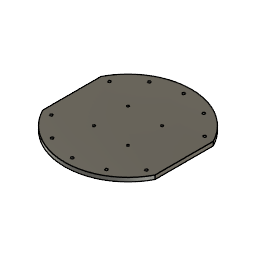
Assembly (Autodesk Fusion 360 archive; units mm, degrees)
design "Upper Chasis"
part number: 2026-04-02-12-40-59-312
Autodesk Fusion 360 part; units mm, degrees
sketch "Sketch1" plane through (0, 0, 0) normal (0, 0, 1) x (-1, 0, 0)
  line L0 (-80, 0) -> (80, 0) construction
  line L1 (-71, -12.5) -> (-10, -12.5)
  line L2 (-10, -12.5) -> (-10, 12.5)
  line L3 (-10, 12.5) -> (-71, 12.5)
  line L4 (-71, 12.5) -> (-71, -12.5)
  line L5 (-71, -36.8646) -> (-71, 36.8646)
  line L6 (0, -80) -> (0, 80) construction
  line L7 (10, -12.5) -> (10, 12.5)
  line L8 (10, 12.5) -> (71, 12.5)
  line L9 (71, -12.5) -> (10, -12.5)
  line L10 (71, 12.5) -> (71, -12.5)
  line L11 (71, -36.8646) -> (71, 36.8646)
  arc A0 (71, 36.8646) -> (-71, 36.8646) centre (0, 0) ccw
  arc A1 (-71, -36.8646) -> (71, -36.8646) centre (0, 0) ccw
  dimension "d6" = 160
  dimension "d7" = 61
  dimension "d8" = 25
  dimension "d9" = 10
  dimension "d10" = 71
  constraint coincident A0.centre A1.centre
  constraint horizontal L0
  constraint horizontal L1
  constraint vertical L2
  constraint horizontal L3
  constraint vertical L4
  constraint symmetric L0 L1 L3
  constraint perpendicular L3 L5
  constraint coincident L6.start A1
  constraint coincident L6.end A0
  constraint vertical L6
  constraint symmetric L1.start L6 L9.start
  constraint symmetric L1.end L6 L7.start
  constraint symmetric L2.end L6 L7.end
  constraint symmetric L3.end L6 L8.end
  constraint symmetric L5.start L6 L11.start
  constraint symmetric L5.end L6 L11.end
  constraint concentric A0 A1
  measures "d6" diameter of A0
  measures "d7" distance of L1.start L1.end
  measures "d8" distance of L1.start L3.end
  measures "d9" distance of A0.centre L2
  measures "d10" distance of A0.centre L5
extrude "Extrude3" add sketch "Sketch1" along normal blind 5
sketch "Sketch3" plane through (0, 0, 5) normal (0, 0, 1) x (-1, 0, 0)
  line L0 (-71, 36.8646) -> (-71, 12.5)
  line L1 (-71, 12.5) -> (-10, 12.5)
  line L2 (-10, 12.5) -> (-10, -12.5)
  line L3 (-10, -12.5) -> (-71, -12.5)
  line L4 (-71, -12.5) -> (-71, -36.8646)
  arc A0 (-71, -36.8646) -> (71, -36.8646) centre (0, 0) ccw
  line L5 (71, -36.8646) -> (71, -12.5)
  line L6 (71, -12.5) -> (10, -12.5)
  line L7 (10, -12.5) -> (10, 12.5)
  line L8 (10, 12.5) -> (71, 12.5)
  line L9 (71, 12.5) -> (71, 36.8646)
  arc A1 (71, 36.8646) -> (-71, 36.8646) centre (0, 0) ccw
  line L10 (-70, 0) -> (70, 0) construction
  line L11 (0, 80) -> (0, -80) construction
  line L12 (21.5, -21.5) -> (-21.5, -21.5)
  line L13 (-21.5, -21.5) -> (-21.5, 21.5)
  line L14 (-21.5, 21.5) -> (21.5, 21.5)
  line L15 (21.5, 21.5) -> (21.5, -21.5)
  point P0 (-60.0095, 36.8646)
  point P1 (-34.3452, 61.4862)
  point P2 (0.0774, 70.4282)
  point P3 (34.4802, 61.4105)
  point P4 (60.0904, 36.7327)
  point P5 (-60.0095, -36.8646)
  point P6 (-34.3452, -61.4862)
  point P7 (0.0774, -70.4282)
  point P8 (34.4802, -61.4105)
  point P9 (60.0904, -36.7327)
  point P10 (21.5, -21.5)
  point P11 (-21.5, -21.5)
  point P12 (21.5, 21.5)
  point P13 (-21.5, 21.5)
  dimension "d20" = -117
  dimension "d25" = 43
  dimension "d26" = 43
  constraint perpendicular L7 L10
  constraint symmetric P0 L10 P5
  constraint symmetric P1 L10 P6
  constraint symmetric P2 L10 P7
  constraint symmetric P3 L10 P8
  constraint symmetric P4 L10 P9
  constraint midpoint A1 L11.start
  constraint midpoint A0 L11.end
  constraint horizontal L12
  constraint vertical L13
  constraint horizontal L14
  constraint vertical L15
  constraint symmetric L11 L13 L15
  constraint symmetric L10 L12 L14
  constraint coincident P10 L12.start
  constraint coincident P11 L12.end
  constraint coincident P12 L14.end
  constraint coincident P13 L13.end
  measures "d25" distance of P10 P11
  measures "d26" distance of P10 P12
hole "Hole2" at (-60.0904, 36.7327, 5) at (-34.4802, 61.4105, 5) at (-0.0774, 70.4282, 5) at (34.3452, 61.4862, 5) at (60.0095, 36.8646, 5) at (-60.0904, -36.7327, 5) at (-34.4802, -61.4105, 5) at (-0.0774, -70.4282, 5) at (34.3452, -61.4862, 5) at (60.0095, -36.8646, 5) direction (0, 0, -1) diameter 3.2 end through all
hole "Hole3" at (-21.5, 21.5, 5) at (21.5, 21.5, 5) at (-21.5, -21.5, 5) at (21.5, -21.5, 5) direction (0, 0, -1) diameter 2.7 end through all
equation "chasis_diameter = 160 mm"
equation "main_layer_thickness = 30 mm"
equation "motor_L = 21 mm"
equation "total_motor_body_length = 61 mm"
equation "standoff_height = 50 mm"
equation "d6 = chasis_diameter"

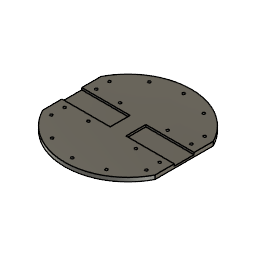
design "Chasis"
part number: 2026-04-02-12-40-59-312
Autodesk Fusion 360 part; units mm, degrees
sketch "Sketch1" plane through (0, 0, 0) normal (0, 0, 1) x (-1, 0, 0)
  line L0 (-80, 0) -> (80, 0) construction
  line L1 (-71, -12.5) -> (-10, -12.5)
  line L2 (-10, -12.5) -> (-10, 12.5)
  line L3 (-10, 12.5) -> (-71, 12.5)
  line L4 (-71, 12.5) -> (-71, -12.5)
  line L5 (-71, -36.8646) -> (-71, 36.8646)
  line L6 (0, -80) -> (0, 80) construction
  line L7 (10, -12.5) -> (10, 12.5)
  line L8 (10, 12.5) -> (71, 12.5)
  line L9 (71, -12.5) -> (10, -12.5)
  line L10 (71, 12.5) -> (71, -12.5)
  line L11 (71, -36.8646) -> (71, 36.8646)
  arc A0 (71, 36.8646) -> (-71, 36.8646) centre (0, 0) ccw
  arc A1 (-71, -36.8646) -> (71, -36.8646) centre (0, 0) ccw
  dimension "d6" = 160
  dimension "d7" = 61
  dimension "d8" = 25
  dimension "d9" = 10
  dimension "d10" = 71
  constraint coincident A0.centre A1.centre
  constraint horizontal L0
  constraint horizontal L1
  constraint vertical L2
  constraint horizontal L3
  constraint vertical L4
  constraint symmetric L0 L1 L3
  constraint perpendicular L3 L5
  constraint coincident L6.start A1
  constraint coincident L6.end A0
  constraint vertical L6
  constraint symmetric L1.start L6 L9.start
  constraint symmetric L1.end L6 L7.start
  constraint symmetric L2.end L6 L7.end
  constraint symmetric L3.end L6 L8.end
  constraint symmetric L5.start L6 L11.start
  constraint symmetric L5.end L6 L11.end
  constraint concentric A0 A1
  measures "d6" diameter of A0
  measures "d7" distance of L1.start L1.end
  measures "d8" distance of L1.start L3.end
  measures "d9" distance of A0.centre L2
  measures "d10" distance of A0.centre L5
extrude "Extrude1" add sketch "Sketch1" along normal blind 5 contours L1 L2 L3 L5 L7 L8 L9 L11 A0 A1
sketch "Sketch2" plane through (0, 0, 5) normal (0, 0, 1) x (-1, 0, 0)
  line L0 (-71, -12.5) -> (-71, -36.8646)
  arc A0 (-71, -36.8646) -> (71, -36.8646) centre (0, 0) ccw
  line L1 (71, -36.8646) -> (71, -12.5)
  line L2 (71, -12.5) -> (10, -12.5)
  line L3 (10, -12.5) -> (10, 12.5)
  line L4 (10, 12.5) -> (71, 12.5)
  line L5 (71, 12.5) -> (71, 36.8646)
  arc A1 (71, 36.8646) -> (-71, 36.8646) centre (0, 0) ccw
  line L6 (-71, 36.8646) -> (-71, 12.5)
  line L7 (-71, 12.5) -> (-10, 12.5)
  line L8 (-10, 12.5) -> (-10, -12.5)
  line L9 (-10, -12.5) -> (-71, -12.5)
  line L10 (-71, 12.5) -> (-10, 12.5)
  line L11 (-10, 12.5) -> (-10, -12.5)
  line L12 (-10, -12.5) -> (-71, -12.5)
  line L13 (10, 12.5) -> (71, 12.5)
  line L14 (10, -12.5) -> (10, 12.5)
  line L15 (71, -12.5) -> (10, -12.5)
  line L16 (-71, -12.5) -> (-71, 12.5)
  line L17 (71, -12.5) -> (71, 12.5)
  constraint coincident L0.start L9.end
  constraint coincident L6.end L7.start
  constraint coincident L1.end L2.start
  constraint coincident L4.end L5.start
extrude "Extrude2" add sketch "Sketch2" against normal blind 2.5 contours L7 L8 L9 L10 L11 L12 L16 | L2 L3 L4 L13 L14 L15 L17
move_body "Move1" bodies 1 to x (1, 0, 0) y (0, -1, 0) z (0, 0, -1) at (0, 0, 0)
move_body "Move2" bodies 1 to x (1, 0, 0) y (0, 1, 0) z (0, 0, 1) at (0, 0, 5)
sketch "Sketch3" plane through (0, 0, 5) normal (0, 0, 1) x (-1, 0, 0)
  line L0 (-71, 36.8646) -> (-71, 12.5)
  line L1 (-71, 12.5) -> (-10, 12.5)
  line L2 (-10, 12.5) -> (-10, -12.5)
  line L3 (-10, -12.5) -> (-71, -12.5)
  line L4 (-71, -12.5) -> (-71, -36.8646)
  arc A0 (-71, -36.8646) -> (71, -36.8646) centre (0, 0) ccw
  line L5 (71, -36.8646) -> (71, -12.5)
  line L6 (71, -12.5) -> (10, -12.5)
  line L7 (10, -12.5) -> (10, 12.5)
  line L8 (10, 12.5) -> (71, 12.5)
  line L9 (71, 12.5) -> (71, 36.8646)
  arc A1 (71, 36.8646) -> (-71, 36.8646) centre (0, 0) ccw
  line L10 (-70, 0) -> (70, 0) construction
  line L11 (0, 80) -> (0, -80) construction
  point P0 (-60.0095, 36.8646)
  point P1 (-34.3452, 61.4862)
  point P2 (0.0774, 70.4282)
  point P3 (34.4802, 61.4105)
  point P4 (60.0904, 36.7327)
  point P5 (-60.0095, -36.8646)
  point P6 (-34.3452, -61.4862)
  point P7 (0.0774, -70.4282)
  point P8 (34.4802, -61.4105)
  point P9 (60.0904, -36.7327)
  point P10 (-60, 20)
  point P11 (-30, 20)
  point P12 (-60, -20)
  point P13 (-30, -20)
  point P14 (60, 20)
  point P15 (30, 20)
  point P16 (60, -20)
  point P17 (30, -20)
  dimension "d20" = -117
  constraint perpendicular L7 L10
  constraint symmetric P0 L10 P5
  constraint symmetric P1 L10 P6
  constraint symmetric P2 L10 P7
  constraint symmetric P3 L10 P8
  constraint symmetric P4 L10 P9
  constraint midpoint A1 L11.start
  constraint midpoint A0 L11.end
  constraint symmetric L10 P10 P12
  constraint symmetric L10 P11 P13
  constraint symmetric P10 L11 P14
  constraint symmetric P11 L11 P15
  constraint symmetric L11 P12 P16
  constraint symmetric L11 P13 P17
hole "Hole1" at (60, -20, 5) at (60.0095, -36.8646, 5) at (34.3452, -61.4862, 5) at (-0.0774, -70.4282, 5) at (-34.4802, -61.4105, 5) at (-30, -20, 5) at (-60, -20, 5) at (-60.0904, -36.7327, 5) at (-30, 20, 5) at (-60, 20, 5) at (-60.0904, 36.7327, 5) at (-34.4802, 61.4105, 5) at (-0.0774, 70.4282, 5) at (30, 20, 5) at (60, 20, 5) at (60.0095, 36.8646, 5) at (34.3452, 61.4862, 5) at (30, -20, 5) direction (0, 0, -1) diameter 3.2 end through all
equation "chasis_diameter = 160 mm"
equation "main_layer_thickness = 30 mm"
equation "motor_L = 21 mm"
equation "total_motor_body_length = 61 mm"
equation "standoff_height = 50 mm"
equation "d6 = chasis_diameter"

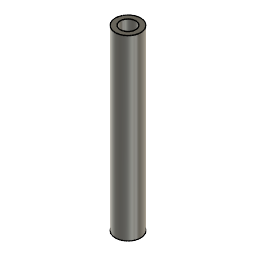
design "support"
part number: 2026-06-24-14-55-54-877
Autodesk Fusion 360 part; units mm, degrees
sketch "Sketch1" plane through (0, 0, 0) normal (0, 0, 1) x (1, 0, 0)
  circle A0 centre (0, 0) radius 2.5
  dimension "d1" = 5
  constraint coincident A0.centre origin
  measures "d1" diameter of A0
extrude "Extrude1" add sketch "Sketch1" along normal blind 35
sketch "Sketch2" plane through (0, 0, 35) normal (0, 0, 1) x (-1, 0, 0)
  circle A0 centre (0, 0) radius 2.5
  constraint coincident A0.centre origin
sketch "Sketch3" plane through (0, 0, 0) normal (0, 0, -1) x (1, 0, 0)
  circle A0 centre (0, 0) radius 2.5
  constraint coincident A0.centre origin
hole "Hole1" at (0, 0, 35) direction (0, 0, -1) diameter 3.05 depth 8 tip angle 180
hole "Hole2" at (0, 0, 0) direction (0, 0, 1) diameter 3.05 depth 8 tip angle 180

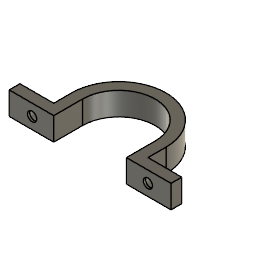
design "Saddle Clamp"
part number: 2026-04-02-17-03-18-147
Autodesk Fusion 360 part; units mm, degrees
sketch "Sketch1" plane through (0, 0, 0) normal (0, 0, 1) x (1, 0, 0)
  line L0 (0, 0) -> (0, 25.1) construction
  line L1 (-28.1, 2.5) -> (-12.6, 2.5)
  line L2 (-12.6, 2.5) -> (-12.6, 12.6)
  line L3 (-16.3497, 12.6) -> (-28.1, 12.6)
  line L4 (-28.1, 12.6) -> (-28.1, 2.5)
  line L5 (28.1, 12.6) -> (28.1, 2.5)
  line L6 (16.3497, 12.6) -> (28.1, 12.6)
  line L7 (28.1, 2.5) -> (12.6, 2.5)
  line L8 (12.6, 2.5) -> (12.6, 12.6)
  arc A0 (16.3497, 12.6) -> (-16.3497, 12.6) centre (0, 12.5) ccw
  arc A1 (12.6, 12.5) -> (-12.6, 12.5) centre (0, 12.5) ccw
  line L9 (-28.1, 12.6) -> (-16.35, 12.6)
  line L10 (-16.35, 12.6) -> (-16.35, 6.25)
  line L11 (-16.35, 6.25) -> (-28.1, 6.25)
  line L12 (-28.1, 6.25) -> (-28.1, 12.6)
  line L13 (28.1, 12.6) -> (16.35, 12.6)
  line L14 (16.35, 6.25) -> (28.1, 6.25)
  line L15 (16.35, 12.6) -> (16.35, 6.25)
  point P0 (0, 12.5)
  point P1 (-12.6, 12.6)
  point P2 (-28.1, 2.5)
  point P3 (12.6, 12.6)
  point P4 (-28.1, 2.5)
  point P5 (-20.1, 6.15)
  point P6 (-16.35, 12.5)
  point P7 (20.1, 6.15)
  dimension "d1" = 25.2
  dimension "d2" = 32.7
  dimension "d3" = 11.75
  dimension "d4" = 6.35
  constraint coincident P0 A0.centre
  constraint coincident L0.start origin
  constraint coincident L0.end A1
  constraint vertical L0
  constraint symmetric P1 L0 L8.end
  constraint horizontal L1
  constraint vertical L2
  constraint horizontal L3
  constraint vertical L4
  constraint coincident P1 L2.end
  constraint coincident P2 L1.start
  constraint symmetric L0 P4 L5.end
  constraint symmetric L0 L1.end L7.end
  constraint symmetric L0 P1 P3
  constraint symmetric L0 L3.end L5.start
  constraint concentric A0 A1
  constraint coincident L2 A1.end
  constraint coincident L8 A1.start
  constraint horizontal L9
  constraint vertical L10
  constraint horizontal L11
  constraint vertical L12
  constraint symmetric L0 L9.end L13.end
  constraint symmetric L0 L10.end L14.start
  constraint symmetric L0 L11.end L14.end
  constraint symmetric L0 P5 P7
  measures "d1" diameter of A1
  measures "d2" diameter of A0
  measures "d3" distance of L3.end L9.end
  measures "d4" distance of L3.end L11.end
extrude "Extrude1" add sketch "Sketch1" along normal blind 8 contours L1 L2 L4 L5 L7 L8 A0 A1 L10 L11 L14 L15
sketch "Sketch2" plane through (0, 6.25, 0) normal (0, 1, 0) x (-1, 0, 0)
  line L0 (16.35, 0) -> (28.1, 0)
  line L1 (28.1, 0) -> (28.1, 8)
  line L2 (28.1, 8) -> (16.35, 8)
  line L3 (16.35, 8) -> (16.35, 0)
  line L4 (0, 8) -> (0, 0) construction
  point P0 (20.1, 4)
  point P1 (-20.1, 4)
  constraint coincident L4.end origin
  constraint vertical L4
  constraint symmetric P0 L4 P1
hole "Hole1" at (-20.1, 6.25, 4) at (20.1, 6.25, 4) direction (0, -1, 0) diameter 3.2 end through all counterbore diameter 6 counterbore depth 3

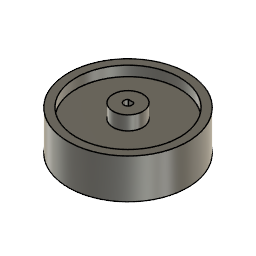
design "Wheel"
part number: 2026-04-02-18-33-10-450
Autodesk Fusion 360 part; units mm, degrees
sketch "Sketch1" plane through (0, 0, 0) normal (0, 0, 1) x (1, 0, 0)
  circle A0 centre (0, 0) radius 30
  circle A1 centre (0, 0) radius 2.05
  line L0 (0, -2.05) -> (0, 1.55) construction
  line L1 (0, 1.55) -> (1.3416, 1.55)
  line L2 (0, 1.55) -> (-1.3416, 1.55)
  dimension "d1" = 60
  dimension "d2" = 4.1
  dimension "d6" = 3.6
  constraint coincident A0.centre A1.centre
  constraint concentric A0 A1
  constraint coincident A1 L0.start
  constraint vertical L0
  constraint coincident A1 L1.end
  constraint perpendicular L0 L1
  constraint coincident A1 L2.end
  constraint perpendicular L0 L2
  measures "d1" diameter of A0
  measures "d2" diameter of A1
  measures "d6" distance of L0.start L0.end
extrude "Extrude1" add sketch "Sketch1" along normal blind 20 contours A0 | A1 L1 L2 picked at (-0.0972, 1.8764)
sketch "Sketch2" plane through (0, 0, 20) normal (0, 0, 1) x (-1, 0, 0)
  line L0 (1.3416, -1.55) -> (-1.3416, -1.55)
  arc A0 (1.3416, -1.55) -> (-1.3416, -1.55) centre (0, 0) ccw
  circle A1 centre (0, 0) radius 30
  circle A2 centre (0, 0) radius 7.5
  circle A3 centre (0, 0) radius 26
  dimension "d7" = 15
  dimension "d8" = 52
  constraint concentric A0 A2
  constraint concentric A0 A3
  measures "d7" diameter of A2
  measures "d8" diameter of A3
extrude "Extrude2" cut sketch "Sketch2" against normal blind 5 contours A3
extrude "Extrude3" add sketch "Sketch2" along normal blind 2 contours A2
sketch "Sketch3" plane through (0, 0, 0) normal (0, 0, 1) x (1, 0, 0)
  circle A0 centre (0, 0) radius 26
  dimension "d14" = 52
  measures "d14" diameter of A0
extrude "Extrude4" cut sketch "Sketch1" sketch "Sketch3" along normal blind 5 contours A1 L1 L2 | A1 L1 L2 of sketch 2

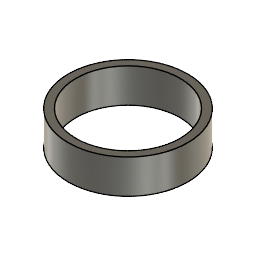
design "Tire"
part number: 2026-04-02-18-46-53-842
Autodesk Fusion 360 part; units mm, degrees
sketch "Sketch1" plane through (0, 0, 0) normal (0, 0, 1) x (1, 0, 0)
  circle A0 centre (0, 0) radius 30.5
  circle A1 centre (0, 0) radius 35
  dimension "d1" = 61
  dimension "d2" = 70
  constraint coincident A0.centre A1.centre
  constraint concentric A0 A1
  measures "d1" diameter of A0
  measures "d2" diameter of A1
extrude "Extrude1" add sketch "Sketch1" along normal blind 20

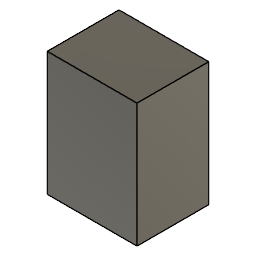
design "Battery"
part number: 2026-05-03-14-36-31-345
Autodesk Fusion 360 part; units mm, degrees
sketch "Sketch1" plane through (0, 0, 0) normal (0, 0, 1) x (1, 0, 0)
  line L0 (-24.8524, 20) -> (25.1476, 20)
  line L1 (25.1476, 20) -> (25.1476, -20)
  line L2 (25.1476, -20) -> (-24.8524, -20)
  line L3 (-24.8524, -20) -> (-24.8524, 20)
  line L4 (-40, 0) -> (40, 0) construction
  line L5 (0.1476, 38.5293) -> (0.1476, -33.2149) construction
  dimension "d1" = 50
  dimension "d2" = 40
  constraint horizontal L0
  constraint vertical L1
  constraint horizontal L2
  constraint vertical L3
  constraint horizontal L4
  constraint perpendicular L4 L5
  constraint symmetric L0 L2 L4
  constraint symmetric L1 L3 L5
  measures "d1" distance of L0.start L0.end
  measures "d2" distance of L0.start L2.end
extrude "Extrude1" add sketch "Sketch1" along normal blind 69

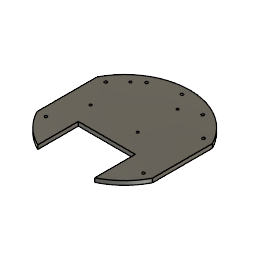
design "Middle Chasis"
part number: 2026-04-02-12-40-59-312
Autodesk Fusion 360 part; units mm, degrees
sketch "Sketch1" plane through (0, 0, 0) normal (0, 0, 1) x (-1, 0, 0)
  line L0 (-80, 0) -> (80, 0) construction
  line L1 (-71, -12.5) -> (-10, -12.5)
  line L2 (-10, -12.5) -> (-10, 12.5)
  line L3 (-10, 12.5) -> (-71, 12.5)
  line L4 (-71, 12.5) -> (-71, -12.5)
  line L5 (-71, -36.8646) -> (-71, 36.8646)
  line L6 (0, -80) -> (0, 80) construction
  line L7 (10, -12.5) -> (10, 12.5)
  line L8 (10, 12.5) -> (71, 12.5)
  line L9 (71, -12.5) -> (10, -12.5)
  line L10 (71, 12.5) -> (71, -12.5)
  line L11 (71, -36.8646) -> (71, 36.8646)
  arc A0 (71, 36.8646) -> (-71, 36.8646) centre (0, 0) ccw
  arc A1 (-71, -36.8646) -> (71, -36.8646) centre (0, 0) ccw
  dimension "d6" = 160
  dimension "d7" = 61
  dimension "d8" = 25
  dimension "d9" = 10
  dimension "d10" = 71
  constraint coincident A0.centre A1.centre
  constraint horizontal L0
  constraint horizontal L1
  constraint vertical L2
  constraint horizontal L3
  constraint vertical L4
  constraint symmetric L0 L1 L3
  constraint perpendicular L3 L5
  constraint coincident L6.start A1
  constraint coincident L6.end A0
  constraint vertical L6
  constraint symmetric L1.start L6 L9.start
  constraint symmetric L1.end L6 L7.start
  constraint symmetric L2.end L6 L7.end
  constraint symmetric L3.end L6 L8.end
  constraint symmetric L5.start L6 L11.start
  constraint symmetric L5.end L6 L11.end
  constraint concentric A0 A1
  measures "d6" diameter of A0
  measures "d7" distance of L1.start L1.end
  measures "d8" distance of L1.start L3.end
  measures "d9" distance of A0.centre L2
  measures "d10" distance of A0.centre L5
extrude "Extrude1" add sketch "Sketch1" along normal blind 5 contours L1 L2 L3 L5 L7 L8 L9 L11 A0 A1
sketch "Sketch2" plane through (0, 0, 5) normal (0, 0, 1) x (-1, 0, 0)
  line L0 (-71, -12.5) -> (-71, -36.8646)
  arc A0 (-71, -36.8646) -> (71, -36.8646) centre (0, 0) ccw
  line L1 (71, -36.8646) -> (71, -12.5)
  line L2 (71, -12.5) -> (10, -12.5)
  line L3 (10, -12.5) -> (10, 12.5)
  line L4 (10, 12.5) -> (71, 12.5)
  line L5 (71, 12.5) -> (71, 36.8646)
  arc A1 (71, 36.8646) -> (-71, 36.8646) centre (0, 0) ccw
  line L6 (-71, 36.8646) -> (-71, 12.5)
  line L7 (-71, 12.5) -> (-10, 12.5)
  line L8 (-10, 12.5) -> (-10, -12.5)
  line L9 (-10, -12.5) -> (-71, -12.5)
  line L10 (-71, 12.5) -> (-10, 12.5)
  line L11 (-10, 12.5) -> (-10, -12.5)
  line L12 (-10, -12.5) -> (-71, -12.5)
  line L13 (10, 12.5) -> (71, 12.5)
  line L14 (10, -12.5) -> (10, 12.5)
  line L15 (71, -12.5) -> (10, -12.5)
  line L16 (-71, -12.5) -> (-71, 12.5)
  line L17 (71, -12.5) -> (71, 12.5)
  constraint coincident L0.start L9.end
  constraint coincident L6.end L7.start
  constraint coincident L1.end L2.start
  constraint coincident L4.end L5.start
extrude "Extrude2" add sketch "Sketch2" against normal blind 2.5 contours L7 L8 L9 L10 L11 L12 L16 | L2 L3 L4 L13 L14 L15 L17
move_body "Move1" bodies 1 to x (1, 0, 0) y (0, -1, 0) z (0, 0, -1) at (0, 0, 0)
move_body "Move2" bodies 1 to x (1, 0, 0) y (0, 1, 0) z (0, 0, 1) at (0, 0, 5)
sketch "Sketch3" plane through (0, 0, 5) normal (0, 0, 1) x (-1, 0, 0)
  line L0 (-71, 36.8646) -> (-71, 12.5)
  line L1 (-71, 12.5) -> (-10, 12.5)
  line L2 (-10, 12.5) -> (-10, -12.5)
  line L3 (-10, -12.5) -> (-71, -12.5)
  line L4 (-71, -12.5) -> (-71, -36.8646)
  arc A0 (-71, -36.8646) -> (71, -36.8646) centre (0, 0) ccw
  line L5 (71, -36.8646) -> (71, -12.5)
  line L6 (71, -12.5) -> (10, -12.5)
  line L7 (10, -12.5) -> (10, 12.5)
  line L8 (10, 12.5) -> (71, 12.5)
  line L9 (71, 12.5) -> (71, 36.8646)
  arc A1 (71, 36.8646) -> (-71, 36.8646) centre (0, 0) ccw
  line L10 (-70, 0) -> (70, 0) construction
  line L11 (0, 80) -> (0, -80) construction
  line L12 (45, -52) -> (-45, -52) construction
  line L13 (-45, -52) -> (-45, -3) construction
  line L14 (-45, -3) -> (45, -3) construction
  line L15 (45, -3) -> (45, -52) construction
  line L16 (45, -52) -> (-13, -52)
  line L17 (-13, -52) -> (-13, -3)
  line L18 (-13, -3) -> (45, -3)
  line L19 (45, -3) -> (45, -52)
  line L20 (35, 22.0908) -> (-35, 22.0908)
  line L21 (-35, 22.0908) -> (-35, 82.0908)
  line L22 (-35, 82.0908) -> (35, 82.0908)
  line L23 (35, 82.0908) -> (35, 22.0908)
  point P0 (-60.0095, 36.8646)
  point P1 (-34.3452, 61.4862)
  point P2 (0.0774, 70.4282)
  point P3 (34.4802, 61.4105)
  point P4 (60.0904, 36.7327)
  point P5 (-60.0095, -36.8646)
  point P6 (-34.3452, -61.4862)
  point P7 (0.0774, -70.4282)
  point P8 (34.4802, -61.4105)
  point P9 (60.0904, -36.7327)
  point P10 (45, -52)
  point P11 (45, -3)
  point P12 (-13, -3)
  point P13 (-13, -52)
  dimension "d20" = -117
  dimension "d25" = 90
  dimension "d26" = 49
  dimension "d27" = 58
  dimension "d28" = 49
  dimension "d29" = 70
  dimension "d30" = 60
  constraint perpendicular L7 L10
  constraint symmetric P0 L10 P5
  constraint symmetric P1 L10 P6
  constraint symmetric P2 L10 P7
  constraint symmetric P3 L10 P8
  constraint symmetric P4 L10 P9
  constraint midpoint A1 L11.start
  constraint midpoint A0 L11.end
  constraint horizontal L12
  constraint vertical L13
  constraint horizontal L14
  constraint vertical L15
  constraint symmetric L11 L13 L15
  constraint horizontal L16
  constraint vertical L17
  constraint horizontal L18
  constraint vertical L19
  constraint coincident P10 L12.start
  constraint coincident P11 L14.end
  constraint coincident P12 L17.end
  constraint coincident P13 L16.end
  constraint horizontal L20
  constraint vertical L21
  constraint horizontal L22
  constraint vertical L23
  constraint symmetric L11 L21 L23
  measures "d25" distance of P10 L12.end
  measures "d26" distance of P10 P11
  measures "d27" distance of P10 P13
  measures "d28" distance of P10 P11
  measures "d29" distance of L20.start L20.end
  measures "d30" distance of L20.start L22.end
extrude "Extrude4" add 2 faces at (30.3333, 4.1667, 2.5) (-50.6667, 4.1667, 2.5) along direction (0, 0, 1) blind 2.5
extrude "Extrude5" cut sketch "Sketch3" against normal blind 5 contours A1 L20 L21 L23
hole "Hole1" at (-60.0904, 36.7327, 5) at (-34.4802, 61.4105, 5) at (-0.0774, 70.4282, 5) at (34.3452, 61.4862, 5) at (60.0095, 36.8646, 5) at (-60.0904, -36.7327, 5) at (60.0095, -36.8646, 5) direction (0, 0, -1) diameter 3.2 end through all
hole "Hole2" at (-45, 52, 5) at (-45, 3, 5) at (13, 3, 5) at (13, 52, 5) direction (0, 0, -1) diameter 2.7 end through all
equation "chasis_diameter = 160 mm"
equation "main_layer_thickness = 30 mm"
equation "motor_L = 21 mm"
equation "total_motor_body_length = 61 mm"
equation "standoff_height = 50 mm"
equation "d6 = chasis_diameter"
